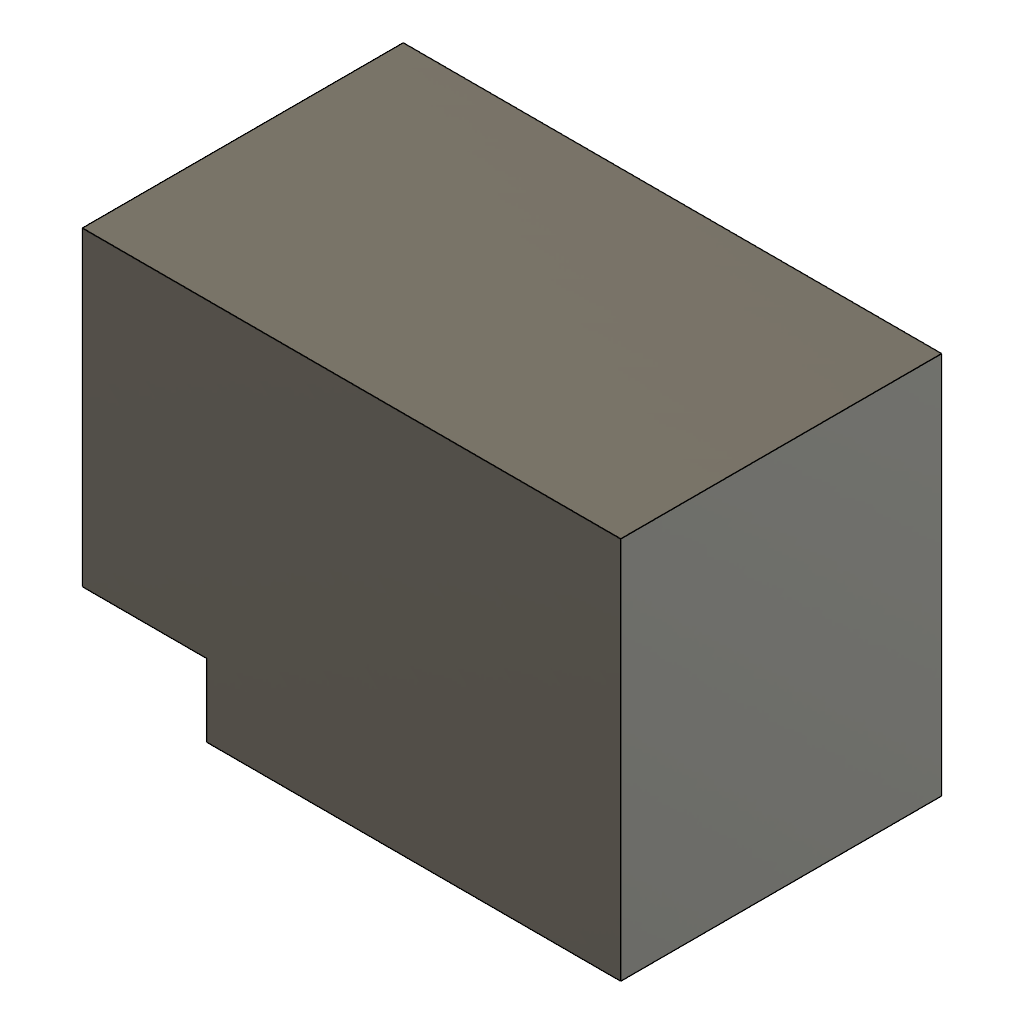
CornerOpposite (Autodesk Fusion 360 design; units mm, degrees)
part number: 2026-11-22-11-52-11-093
Autodesk Fusion 360 part; units mm, degrees
sketch "Base sketch" plane through (0, 0, 0) normal (0, 0, 1) x (1, 0, 0)
  line L0 (-20, -10) -> (32, -10)
  line L1 (32, -10) -> (32, 27)
  line L2 (32, 27) -> (-20, 27)
  line L3 (-20, 27) -> (-20, -10)
extrude "Base" add sketch "Base sketch" along normal blind 31
sketch "Corner sketch" plane through (0, 0, 0) normal (0, 0, 1) x (1, 0, 0)
  line L0 (-30, -20) -> (-8, -20)
  line L1 (-8, -20) -> (-8, -3)
  line L2 (-8, -3) -> (-30, -3)
  line L3 (-30, -3) -> (-30, -20)
extrude "Corner" cut sketch "Corner sketch" along normal blind 31
